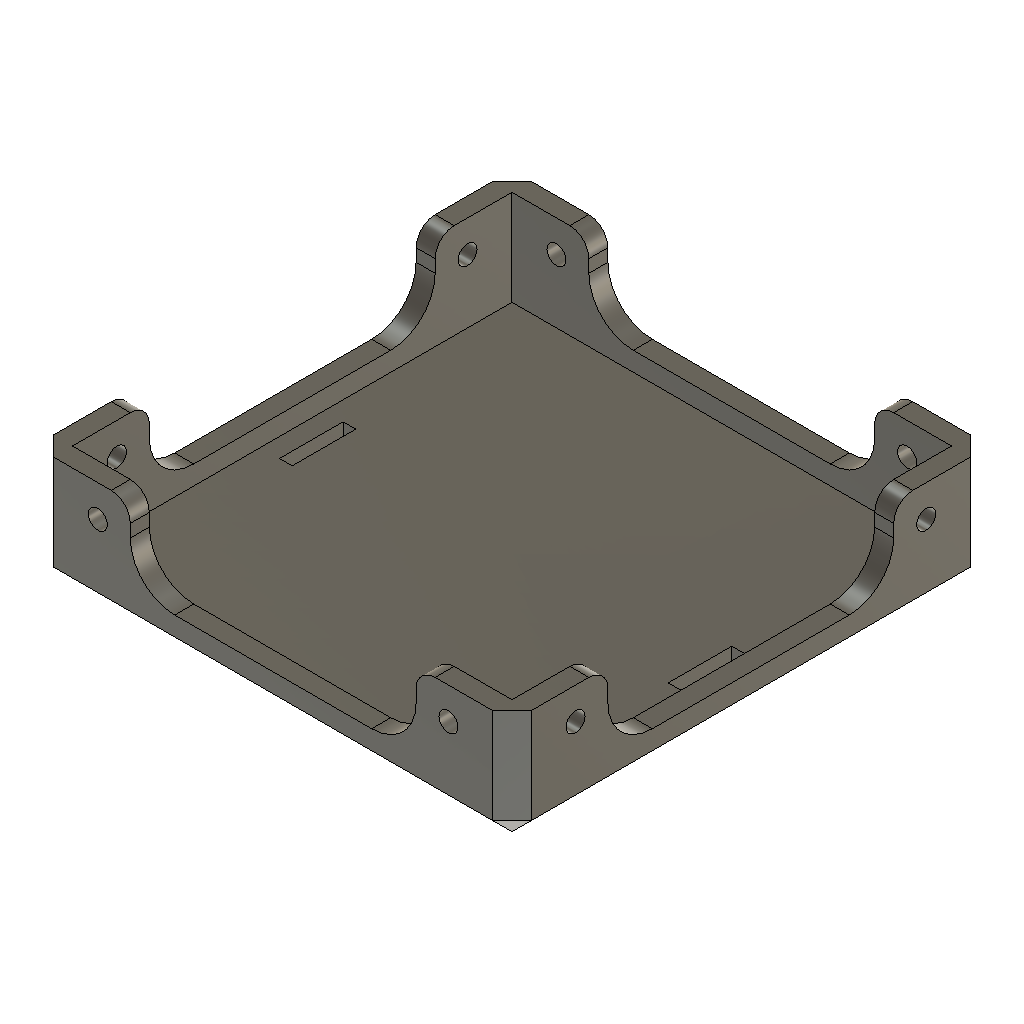
Topo_Soccer_v1 (Autodesk Fusion 360 design; units mm, degrees)
Autodesk Fusion 360 part; units mm, degrees
sketch "Esboço1" plane through (0, 0, 0) normal (0, 0, 1) x (1, 0, 0)
  line L0 (0, 0) -> (69.2, 0)
  line L1 (69.2, 0) -> (69.2, -69.2)
  line L2 (69.2, -69.2) -> (0, -69.2)
  line L3 (0, -69.2) -> (0, 0)
  line L4 (-3, 3) -> (72.2, 3)
  line L5 (72.2, 3) -> (72.2, -72.2)
  line L6 (72.2, -72.2) -> (-3, -72.2)
  line L7 (-3, -72.2) -> (-3, 3)
  dimension "d1" = 69.2
  dimension "d2" = 69.2
  dimension "d3" = 3
  dimension "d4" = 3
  dimension "d5" = 3
  dimension "d6" = 3
  constraint horizontal L0
  constraint vertical L1
  constraint horizontal L2
  constraint vertical L3
  constraint coincident L0.start L3.end
  constraint horizontal L4
  constraint vertical L5
  constraint horizontal L6
  constraint vertical L7
  measures "d1" distance of L0.start L0.end
  measures "d2" distance of L0.start L2.end
  measures "d3" distance of L0 L4
  measures "d4" distance of L2 L6
  measures "d5" distance of L1 L5
  measures "d6" distance of L3 L7
extrude "Extrusão1" add sketch "Esboço1" along normal blind 15
sketch "Esboço2" plane through (0, 3, 0) normal (0, 1, 0) x (-1, 0, 0)
  line L0 (-72.2, 0) -> (3, 0)
  line L1 (3, 0) -> (3, 15)
  line L2 (3, 15) -> (-72.2, 15)
  line L3 (-72.2, 15) -> (-72.2, 0)
  line L4 (-57.1, 3) -> (-12.1, 3)
  line L5 (-12.1, 3) -> (-12.1, 27)
  line L6 (-12.1, 27) -> (-57.1, 27)
  line L7 (-57.1, 27) -> (-57.1, 3)
  line L8 (-57.1, 3) -> (-12.1, 27) construction
  line L9 (-12.1, 3) -> (-57.1, 27) construction
  circle A0 centre (-7, 10) radius 1.5
  circle A1 centre (-62.2, 10) radius 1.5
  point P0 (-34.6, 15)
  dimension "d9" = 45
  dimension "d11" = 3
  dimension "d12" = 3
  dimension "d13" = 3
  dimension "d14" = 10
  dimension "d15" = 10
  dimension "d16" = 10
  dimension "d17" = 10
  constraint horizontal L4
  constraint perpendicular L4 L5
  constraint parallel L4 L6
  constraint parallel L5 L7
  constraint coincident L8 P0
  constraint coincident L9 P0
  constraint midpoint L2 P0
  measures "d9" distance of L5.end L6.end
  measures "d11" distance of L0 L4
  measures "d12" diameter of A0
  measures "d13" diameter of A1
  measures "d14" distance of L0 A1.centre
  measures "d15" distance of L3 A1.centre
  measures "d16" distance of L0 A0.centre
  measures "d17" distance of L1 A0.centre
extrude "Extrusão2" cut sketch "Esboço2" against normal blind 84 contours L2 L5 L6 L7 | L2 L4 L5 L7 | A0 | A1
sketch "Esboço3" plane through (72.2, 0, 0) normal (1, 0, 0) x (0, 1, 0)
  line L0 (-72.2, 0) -> (3, 0)
  circle A0 centre (-7, 10) radius 1.5
  line L1 (-12.1, 3) -> (-57.1, 27) construction
  line L2 (-57.1, 3) -> (-12.1, 27) construction
  circle A1 centre (-62.2, 10) radius 1.5
  line L3 (-12.1, 3) -> (-12.1, 27)
  line L4 (-57.1, 27) -> (-57.1, 3)
  line L5 (-57.1, 3) -> (-12.1, 3)
  line L6 (-12.1, 27) -> (-57.1, 27)
  line L7 (-72.2, 15) -> (-72.2, 0)
  line L8 (3, 15) -> (-72.2, 15)
  line L9 (3, 0) -> (3, 15)
  point P0 (-34.6, 15)
  dimension "d30" = 45
  dimension "d31" = 3
  dimension "d32" = 3
  dimension "d33" = 3
  dimension "d34" = 10
  dimension "d35" = 10
  dimension "d36" = 10
  dimension "d37" = 10
  constraint horizontal L5
  constraint perpendicular L3 L5
  constraint parallel L5 L6
  constraint parallel L3 L4
  constraint coincident P0 L2
  constraint coincident P0 L1
  constraint midpoint P0 L8
  measures "d30" distance of L2.end L1.end
  measures "d31" distance of L0 L5
  measures "d32" diameter of A0
  measures "d33" diameter of A1
  measures "d34" distance of A1.centre L0
  measures "d35" distance of A1.centre L7
  measures "d36" distance of A0.centre L0
  measures "d37" distance of A0.centre L9
extrude "Extrusão4" cut sketch "Esboço3" against normal blind 78 contours L3 L4 L5 L8 | A0 | A1
sketch "Esboço4" plane through (0, 0, 0) normal (0, 0, -1) x (1, 0, 0)
  line L0 (0, 69.2) -> (69.2, 69.2)
  line L1 (69.2, 69.2) -> (69.2, 0)
  line L2 (69.2, 0) -> (0, 0)
  line L3 (0, 0) -> (0, 69.2)
  line L4 (72.2, 72.2) -> (-3, 72.2)
  line L5 (-3, 72.2) -> (-3, -3)
  line L6 (-3, -3) -> (72.2, -3)
  line L7 (72.2, -3) -> (72.2, 72.2)
  line L8 (-3, 72.2) -> (72.2, 72.2)
  line L9 (72.2, 72.2) -> (72.2, -3)
  line L10 (72.2, -3) -> (-3, -3)
  line L11 (-3, -3) -> (-3, 72.2)
  line L12 (3, 39.6) -> (5, 39.6)
  line L13 (5, 39.6) -> (5, 29.6)
  line L14 (5, 29.6) -> (3, 29.6)
  line L15 (3, 29.6) -> (3, 39.6)
  line L16 (64.2, 39.6) -> (66.2, 39.6)
  line L17 (66.2, 39.6) -> (66.2, 29.6)
  line L18 (66.2, 29.6) -> (64.2, 29.6)
  line L19 (64.2, 29.6) -> (64.2, 39.6)
  dimension "d42" = 2
  dimension "d43" = 2
  dimension "d44" = 10
  dimension "d45" = 10
  dimension "d46" = 32.6
  dimension "d47" = 32.6
  dimension "d48" = 6
  dimension "d49" = 6
  constraint horizontal L8
  constraint vertical L9
  constraint horizontal L10
  constraint vertical L11
  constraint coincident L6.end L7.start
  constraint coincident L4.end L5.start
  constraint horizontal L12
  constraint vertical L13
  constraint horizontal L14
  constraint vertical L15
  constraint horizontal L16
  constraint vertical L17
  constraint horizontal L18
  constraint vertical L19
  measures "d42" distance of L16.start L16.end
  measures "d43" distance of L12.start L12.end
  measures "d44" distance of L12.end L13.end
  measures "d45" distance of L16.end L17.end
  measures "d46" distance of L8 L16
  measures "d47" distance of L8 L12
  measures "d48" distance of L11 L15
  measures "d49" distance of L9 L17
extrude "Extrusão5" add sketch "Esboço4" along normal blind 3 contours L0 L1 L2 L3 | L4 L5 L6 L7 L8 L9 L10 L11
chamfer "Chanfro1" distance 3 angle 45 8 edges at (34.6, 3, -3) (-3, -34.6, -3) (34.6, -72.2, -3) (72.2, -34.6, -3) (72.2, 3, 6) (-3, 3, 6) (-3, -72.2, 6) (72.2, -72.2, 6) tangent chain off
fillet "Arredondamento1" radius 7 8 edges at (12.1, -70.7, 3) (-1.5, -57.1, 3) (57.1, -70.7, 3) (70.7, -57.1, 3) (70.7, -12.1, 3) (-1.5, -12.1, 3) (12.1, 1.5, 3) (57.1, 1.5, 3)
fillet "Arredondamento2" radius 3 8 edges at (57.1, -70.7, 15) (70.7, -57.1, 15) (12.1, -70.7, 15) (-1.5, -57.1, 15) (-1.5, -12.1, 15) (12.1, 1.5, 15) (57.1, 1.5, 15) (70.7, -12.1, 15)
